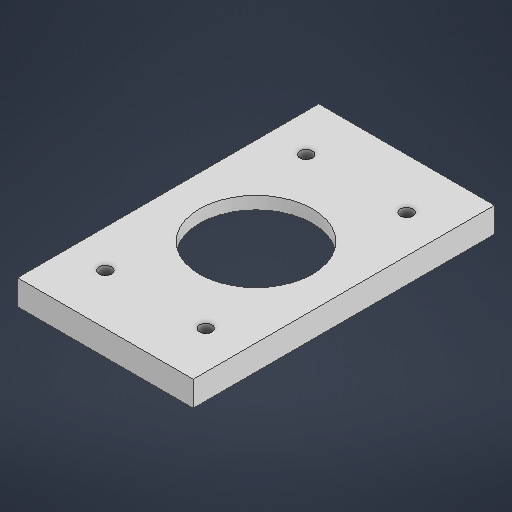
# Autodesk Inventor part: lien_arbre_exterieur_U
Saved by Autodesk Inventor 2026.1 (Build 301233020, 233B)
## iProperties
Created: 2026-11-20
Part Number: lien_arbre_exterieur_U
Material: Generic
Document SubType Name: Modeling
Designer: matar
Density: 1 g/cm^3
Appearance: Default
Author: matar
Autodesk Inventor part; units mm, degrees
ref_plane "YZ Plane" through (0, 0, 0) normal (1, 0, 0) x (0, 1, 0)
ref_plane "XZ Plane" through (0, 0, 0) normal (0, 1, 0) x (-1, 0, 0)
ref_plane "XY Plane" through (0, 0, 0) normal (0, 0, 1) x (1, 0, 0)
sketch "Sketch1" plane through (0, 0, 0) normal (0, 1, 0) x (-1, 0, 0)
  line L0 (0, 0) -> (70, 0)
  line L1 (70, 0) -> (70, -120)
  line L2 (70, -120) -> (0, -120)
  line L3 (0, -120) -> (0, 0)
  circle A0 centre (35, -60) radius 30
  dimension "d0" = 120
  dimension "d1" = 70
  dimension "d2" = 60
  dimension "d5" = 60
  constraints: 8 end point, 2 parallel, 1 centre point, 1 horizontal, 1 perpendicular
  measures "d0" distance of L0.end L1.end
  measures "d1" distance of L1.end L2.end
  measures "d2" diameter of A0
  measures "d5" distance from line of L2 A0.centre
extrude "Extrusion1" add sketch "Sketch1" along normal blind 5
sketch "Sketch2" plane through (0, 5, 0) normal (0, 1, 0) x (1, 0, 0)
  circle A0 centre (-35, 60) radius 30 projected
  circle A1 centre (-35, 60) radius 22.5
  line L0 (-70, 0) -> (0, 0) projected
  line L1 (0, 120) -> (-70, 120) projected
  line L2 (-70, 0) -> (0, 0)
  line L3 (0, 0) -> (0, 120)
  line L4 (0, 120) -> (-70, 120)
  line L5 (-70, 120) -> (-70, 0)
  dimension "d6" = 45
  constraints: 8 end point, 2 parallel, 1 centre point, 1 coincident, 1 horizontal, 1 perpendicular
  measures "d6" diameter of A1
extrude "Extrusion2" add sketch "Sketch2" along normal blind 5 contours A0 | L5 L1 L3 L0
sketch "Sketch3" plane through (0, 10, 0) normal (0, 1, 0) x (1, 0, 0)
  circle A0 centre (-15, 100) radius 2.5
  circle A1 centre (-15, 20) radius 2.5
  circle A2 centre (-55, 20) radius 2.5
  circle A3 centre (-55, 100) radius 2.5
  line L0 (0, 120) -> (-70, 120) projected
  line L1 (-70, 0) -> (0, 0) projected
  line L2 (0, 0) -> (0, 120) projected
  line L3 (-70, 120) -> (-70, 0) projected
  dimension "d9" = 5
  dimension "d11" = 20
  dimension "d12" = 20
  dimension "d13" = 15
  dimension "d14" = 15
  dimension "d15" = 20
  dimension "d16" = 20
  dimension "d17" = 15
  dimension "d18" = 15
  constraints: 4 centre point
  measures "d9" diameter of A0
  measures "d11" distance from line of L0 A0.centre
  measures "d12" distance from line of L1 A1.centre
  measures "d13" distance from line of L2 A1.centre
  measures "d14" distance from line of L3 A2.centre
  measures "d15" distance from line of L1 A2.centre
  measures "d16" distance from line of L0 A3.centre
  measures "d17" distance from line of L3 A3.centre
  measures "d18" distance from line of L2 A0.centre
extrude "Extrusion3" cut sketch "Sketch3" against normal through all contours A0 | A1 | A2 | A3
body "Solid1"
